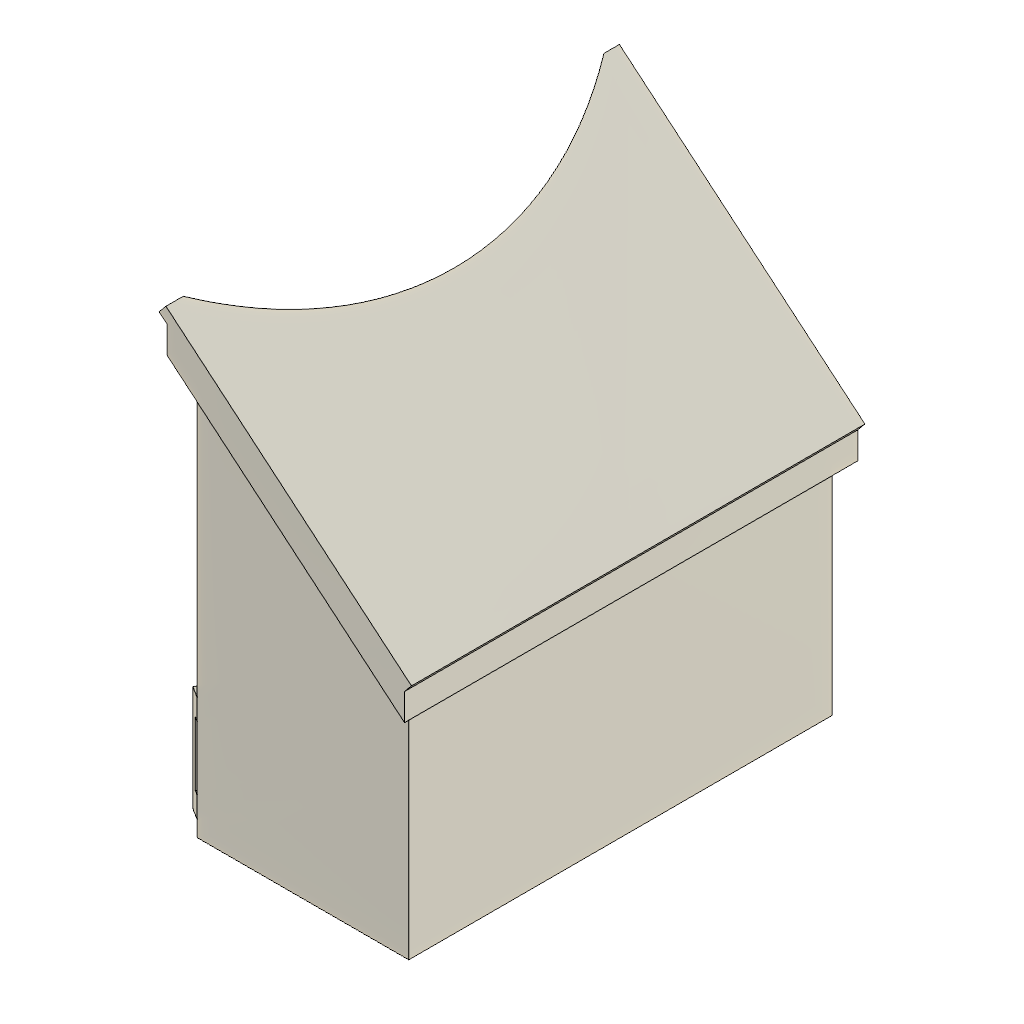
Tide Sensor Housing (Autodesk Fusion 360 design; units mm, degrees)
Autodesk Fusion 360 part; units mm, degrees
sketch "Sketch1" plane through (0, 0, 0) normal (0, 0, 1) x (1, 0, 0)
  line L0 (0, 0) -> (101.6, 0)
  line L1 (101.6, 0) -> (101.6, 203.2)
  line L2 (101.6, 203.2) -> (0, 203.2)
  line L3 (0, 203.2) -> (0, 0)
  circle A0 centre (-163.8957, 102.023) radius 193.04
  circle A1 centre (88.9, 119.38) radius 0.762
  circle A2 centre (88.9, 83.82) radius 0.762
  circle A3 centre (63.5, 119.38) radius 0.762
  circle A4 centre (63.5, 83.82) radius 0.762
  circle A5 centre (76.2, 101.6) radius 12.7
  line L4 (50.8, 127) -> (279.4, 127)
  line L5 (279.4, 127) -> (279.4, 76.2)
  line L6 (279.4, 76.2) -> (50.8, 76.2)
  line L7 (50.8, 76.2) -> (50.8, 127)
  line L8 (33.02, 175.26) -> (46.736, 175.26)
  line L9 (46.736, 175.26) -> (46.736, 180.34)
  line L10 (46.736, 180.34) -> (33.02, 180.34)
  line L11 (33.02, 180.34) -> (33.02, 175.26)
  line L12 (33.02, 175.26) -> (38.1, 175.26)
  line L13 (38.1, 175.26) -> (38.1, 165.1)
  line L14 (38.1, 165.1) -> (33.02, 165.1)
  line L15 (33.02, 165.1) -> (33.02, 175.26)
  line L16 (46.736, 175.26) -> (41.656, 175.26)
  line L17 (41.656, 175.26) -> (41.656, 165.1)
  line L18 (41.656, 165.1) -> (46.736, 165.1)
  line L19 (46.736, 165.1) -> (46.736, 175.26)
  line L20 (46.736, 180.34) -> (33.02, 180.34)
  line L21 (33.02, 175.26) -> (46.736, 175.26)
  line L22 (33.02, 180.34) -> (33.02, 175.26)
  line L23 (46.736, 175.26) -> (46.736, 180.34)
  line L24 (46.736, 165.1) -> (46.736, 175.26)
  line L25 (41.656, 175.26) -> (41.656, 165.1)
  line L26 (41.656, 165.1) -> (46.736, 165.1)
  line L27 (38.1, 175.26) -> (38.1, 165.1)
  line L28 (33.02, 165.1) -> (33.02, 175.26)
  line L29 (38.1, 165.1) -> (33.02, 165.1)
  line L30 (-163.8957, 102.023) -> (344.1043, 102.023)
  line L31 (38.1, 28.7859) -> (38.1, 38.9459)
  line L32 (33.02, 38.9459) -> (33.02, 28.7859)
  line L33 (33.02, 28.7859) -> (46.736, 28.7859)
  line L34 (38.1, 38.9459) -> (33.02, 38.9459)
  line L35 (41.656, 28.7859) -> (41.656, 38.9459)
  line L36 (41.656, 38.9459) -> (46.736, 38.9459)
  line L37 (46.736, 38.9459) -> (46.736, 28.7859)
  line L38 (46.736, 28.7859) -> (46.736, 23.7059)
  line L39 (46.736, 23.7059) -> (33.02, 23.7059)
  line L40 (33.02, 23.7059) -> (33.02, 28.7859)
  circle A6 centre (-163.8957, 102.023) radius 190.5
  circle A7 centre (-163.8957, 102.023) radius 186.69
  line L41 (-163.8957, 102.023) -> (0.9543, 203.8135)
  line L42 (-163.8957, 102.023) -> (0, 0)
  line L43 (-163.8957, 102.023) -> (19.05, 196.85)
  line L44 (-163.8957, 102.023) -> (19.05, 6.35)
  line L45 (4.9142, 13.7424) -> (7.165, 12.5654)
  line L46 (1.538, 15.508) -> (4.9142, 13.7424)
  line L47 (1.538, 15.508) -> (4.9142, 13.7424)
  line L48 (-163.8957, 102.023) -> (4.9142, 13.7424)
  point P0 (1.538, 15.508)
  point P1 (4.9142, 13.7424)
  point P2 (7.165, 12.5654)
  dimension "d1" = 101.6
  dimension "d2" = 203.2
  dimension "d3" = 386.08
  dimension "d4" = 1.524
  dimension "d5" = 1.524
  dimension "d6" = 1.524
  dimension "d7" = 1.524
  dimension "d8" = 25.4
  dimension "d9" = 228.6
  dimension "d10" = 50.8
  dimension "d76" = 13.716
  dimension "d77" = 5.08
  dimension "d78" = 5.08
  dimension "d79" = 10.16
  dimension "d80" = 5.08
  dimension "d81" = 10.16
  dimension "d82" = 13.716
  dimension "d83" = 5.08
  dimension "d84" = 5.08
  dimension "d85" = 10.16
  dimension "d86" = 5.08
  dimension "d87" = 10.16
  dimension "d88" = 508
  dimension "d89" = 13.716
  dimension "d90" = 5.08
  dimension "d91" = 10.16
  dimension "d92" = 13.716
  dimension "d93" = 5.08
  dimension "d94" = 5.08
  dimension "d95" = 10.16
  dimension "d96" = 5.08
  dimension "d97" = 10.16
  dimension "d109" = 381
  dimension "d110" = 373.38
  constraint horizontal L0
  constraint vertical L1
  constraint horizontal L2
  constraint vertical L3
  constraint coincident L0.start L3.end
  constraint horizontal L4
  constraint vertical L5
  constraint horizontal L6
  constraint vertical L7
  constraint horizontal L8
  constraint vertical L9
  constraint horizontal L10
  constraint vertical L11
  constraint horizontal L12
  constraint vertical L13
  constraint horizontal L14
  constraint vertical L15
  constraint horizontal L16
  constraint vertical L17
  constraint horizontal L18
  constraint vertical L19
  constraint horizontal L21
  constraint vertical L23
  constraint horizontal L20
  constraint vertical L22
  constraint vertical L27
  constraint horizontal L29
  constraint vertical L28
  constraint vertical L25
  constraint horizontal L26
  constraint vertical L24
  constraint coincident A0.centre L30.start
  constraint perpendicular L5 L30
  constraint concentric A0 A6
  constraint concentric A0 A7
  constraint coincident A7 P0
  constraint coincident L44 P0
  constraint coincident A6 P1
  constraint coincident L44 P1
  constraint coincident L44 P2
  constraint coincident A0 P2
  constraint coincident P1 L45.start
  constraint coincident P2 L45.end
  constraint coincident P0 L46.start
  measures "d1" distance of L0.start L0.end
  measures "d2" distance of L0.start L2.end
  measures "d3" diameter of A0
  measures "d4" diameter of A1
  measures "d5" diameter of A2
  measures "d6" diameter of A3
  measures "d7" diameter of A4
  measures "d8" diameter of A5
  measures "d9" distance of L4.start L4.end
  measures "d10" distance of L4.start L6.end
  measures "d76" distance of L8.start L8.end
  measures "d77" distance of L8.start L10.end
  measures "d78" distance of L8.start L12.end
  measures "d79" distance of L8.start L14.end
  measures "d80" distance of L8.end L16.end
  measures "d81" distance of L8.end L18.end
  measures "d82" distance of L8.start L8.end
  measures "d83" distance of L10.end L8.start
  measures "d84" distance of L8.start L12.end
  measures "d85" distance of L8.start L14.end
  measures "d86" distance of L8.end L16.end
  measures "d87" distance of L8.end L18.end
  measures "d88" distance of A0.centre L30.end
  measures "d89" distance of L32.end L33.end
  measures "d90" distance of L39.end L32.end
  measures "d91" distance of L32.end L32.start
  measures "d92" distance of L32.end L33.end
  measures "d93" distance of L39.end L32.end
  measures "d94" distance of L32.end L31.start
  measures "d95" distance of L32.end L32.start
  measures "d96" distance of L33.end L35.start
  measures "d97" distance of L33.end L36.end
  measures "d109" diameter of A6
  measures "d110" diameter of A7
extrude "Extrude1" add sketch "Sketch1" along normal blind 203.2 thin wall 5.08 inside contours L0 L1 L3 A0 L6 L7 L30 | L1 A5 L6 L7 L30 | L1 A5 L4 L7 L30 | L1 L2 A0 L4 L7 L30 | A5 L30 | A5 L30 | A1 | A2 | A3 | A4 | L8 L9 L10 L11 L12 L16 L20 L21 L22 L23 | L8 L12 L13 L14 L15 L21 L27 L28 L29 | L8 L16 L17 L18 L19 L21 L24 L25 L26 | L31 L32 L33 L34 | L33 L38 L39 L40 | L33 L35 L36 L37 makes body 1
extrude "Extrude2" add sketch "Sketch1" against normal blind 7.62 contours L0 L1 L3 A0 L6 L7 L30 | L1 A5 L6 L7 L30 | L1 A5 L4 L7 L30 | L1 L2 A0 L4 L7 L30 | L8 L9 L10 L11 L12 L16 L20 L21 L22 L23 | L8 L12 L13 L14 L15 L21 L27 L28 L29 | L8 L16 L17 L18 L19 L21 L24 L25 L26 | L31 L32 L33 L34 | L33 L38 L39 L40 | L33 L35 L36 L37 bodies 1
sketch "Sketch2" plane through (0, 0, 0) normal (0, 0, 1) x (1, 0, 0)
  line L0 (0, 0) -> (228.6, 0)
  line L1 (228.6, 0) -> (228.6, 50.8)
  line L2 (228.6, 50.8) -> (0, 50.8)
  line L3 (0, 50.8) -> (0, 0)
  circle A0 centre (25.4, 25.4) radius 12.7
  circle A1 centre (203.2, 25.4) radius 8.128
  circle A2 centre (203.2, 25.4) radius 8.128
  line L4 (228.6, 50.8) -> (0, 50.8)
  circle A3 centre (25.4, 127) radius 12.7
  line L5 (-5.08, 96.52) -> (233.68, 96.52)
  line L6 (233.68, 96.52) -> (233.68, 157.48)
  line L7 (233.68, 157.48) -> (-5.08, 157.48)
  line L8 (-5.08, 157.48) -> (-5.08, 96.52)
  circle A4 centre (220.98, 43.18) radius 5.08
  circle A5 centre (220.98, 7.62) radius 5.08
  circle A6 centre (220.98, 43.18) radius 1.651
  circle A7 centre (220.98, 7.62) radius 1.651
  circle A8 centre (55.88, 7.62) radius 5.08
  circle A9 centre (55.88, 7.62) radius 1.651
  circle A10 centre (55.88, 43.18) radius 5.08
  circle A11 centre (55.88, 43.18) radius 1.651
  circle A12 centre (220.98, 144.78) radius 2.54
  circle A13 centre (220.98, 109.22) radius 2.54
  circle A14 centre (55.88, 144.78) radius 2.54
  circle A15 centre (55.88, 109.22) radius 2.54
  line L9 (-5.08, 157.48) -> (-5.08, 96.52)
  line L10 (233.68, 157.48) -> (-5.08, 157.48)
  circle A16 centre (25.4, 127) radius 12.7
  circle A17 centre (220.98, 109.22) radius 2.54
  circle A18 centre (220.98, 144.78) radius 2.54
  circle A19 centre (55.88, 144.78) radius 2.54
  circle A20 centre (55.88, 109.22) radius 2.54
  circle A21 centre (12.7, 144.78) radius 1.27
  circle A22 centre (38.1, 144.78) radius 1.27
  circle A23 centre (12.7, 109.22) radius 1.27
  circle A24 centre (38.1, 109.22) radius 1.27
  dimension "d20" = 228.6
  dimension "d21" = 50.8
  dimension "d22" = 25.4
  dimension "d23" = 16.256
  dimension "d24" = 16.256
  dimension "d28" = 25.4
  dimension "d29" = 10.16
  dimension "d30" = 10.16
  dimension "d31" = 3.302
  dimension "d32" = 3.302
  dimension "d33" = 10.16
  dimension "d34" = 10.16
  dimension "d35" = 3.302
  dimension "d36" = 3.302
  dimension "d37" = 5.08
  dimension "d38" = 5.08
  dimension "d40" = 5.08
  dimension "d41" = 5.08
  dimension "d53" = 25.4
  dimension "d54" = 5.08
  dimension "d55" = 5.08
  dimension "d56" = 5.08
  dimension "d57" = 5.08
  dimension "d63" = 2.54
  dimension "d64" = 2.54
  dimension "d65" = 2.54
  dimension "d66" = 2.54
  constraint horizontal L0
  constraint vertical L1
  constraint horizontal L2
  constraint vertical L3
  constraint coincident L0.start L3.end
  constraint horizontal L4
  constraint horizontal L5
  constraint vertical L6
  constraint horizontal L7
  constraint vertical L8
  constraint concentric A4 A6
  constraint concentric A5 A7
  constraint concentric A10 A11
  constraint concentric A8 A9
  constraint horizontal L10
  constraint vertical L9
  measures "d20" distance of L0.start L0.end
  measures "d21" distance of L0.start L2.end
  measures "d22" diameter of A0
  measures "d23" diameter of A1
  measures "d24" diameter of A2
  measures "d28" diameter of A3
  measures "d29" diameter of A4
  measures "d30" diameter of A5
  measures "d31" diameter of A6
  measures "d32" diameter of A7
  measures "d33" diameter of A10
  measures "d34" diameter of A8
  measures "d35" diameter of A11
  measures "d36" diameter of A9
  measures "d37" diameter of A12
  measures "d38" diameter of A13
  measures "d40" diameter of A14
  measures "d41" diameter of A15
  measures "d53" diameter of A16
  measures "d54" diameter of A18
  measures "d55" diameter of A17
  measures "d56" diameter of A19
  measures "d57" diameter of A20
  measures "d63" diameter of A21
  measures "d64" diameter of A22
  measures "d65" diameter of A23
  measures "d66" diameter of A24
extrude "Extrude12" add sketch "Sketch1" along normal blind 76.2 separate body contours L8 L9 L10 L11 L12 L16 L20 L21 L22 L23 | L8 L12 L13 L14 L15 L21 L27 L28 L29 | L8 L16 L17 L18 L19 L21 L24 L25 L26 | L31 L32 L33 L34 | L33 L38 L39 L40 | L33 L35 L36 L37 makes body 2 at (33.02, 175.26, 25.4) makes body 3 at (33.02, 33.8659, 50.8)
sketch "Sketch3" plane through (0, 0, 0) normal (0, 1, 0) x (1, 0, 0)
  line L0 (0.3158, -203.2) -> (155.9761, -72.5856)
  line L1 (0.3158, -203.2) -> (203.5158, -203.2) construction
  line L2 (0.3158, -203.2) -> (101.6, -203.2)
  line L3 (101.6, 0) -> (101.6, -203.2)
  line L4 (101.6, -111.76) -> (101.6, -203.2)
  point P0 (101.6, -203.2)
  point P1 (101.6, -203.2)
  dimension "d105" = 40
  dimension "d106" = 203.2
  constraint horizontal L1
  constraint coincident L3 L4.start
  measures "d105" angle of L0 L1
  measures "d106" distance of L0.start L0.end
extrude "Extrude4" add sketch "Sketch2" along normal blind 25.4 thin wall 5.08 inside separate body contours L0 L1 L2 L3 L4 | A0 | A1 A2 | A4 | A5 | A6 | A7 | A8 | A9 | A10 | A11 makes body 4
extrude "Extrude5" add sketch "Sketch2" against normal blind 5.08 separate body contours L0 L1 L2 L3 L4 | A0 | A4 | A5 | A6 | A7 | A8 | A9 | A10 | A11 makes body 5
extrude "Extrude6" add sketch "Sketch2" along normal blind 25.4 contours A4 | A5 | A8 | A10 bodies 4 5
extrude "Extrude9" add sketch "Sketch2" along normal blind 5.08 separate body contours L5 L6 L7 L8 L9 L10 makes body 6
extrude "Extrude10" add sketch "Sketch2" against normal blind 10.16 thin wall 5.08 inside separate body contours A3 A16 | L5 L6 L7 L8 L9 L10 | A12 A18 | A13 A17 | A14 A19 | A15 A20 | A21 | A22 | A23 | A24 makes body 7
sketch "Sketch4" plane through (0, 0, 0) normal (0, -1, 0) x (1, 0, 0)
  line L0 (101.6, -7.62) -> (101.6, 203.2)
  line L1 (101.6, 203.2) -> (0, 203.2)
  line L2 (0, -7.62) -> (101.6, -7.62)
  line L3 (-25.4, 224.5131) -> (139.7, 85.9778)
  line L4 (0, 203.2) -> (152.5992, 203.2) construction
  line L5 (0, 203.2) -> (0, -7.62)
  line L6 (116.7452, 94.5635) -> (116.7452, 105.2392)
  line L7 (-25.4, 228.6) -> (139.7, 228.6)
  line L8 (139.7, 228.6) -> (139.7, -12.3567)
  line L9 (139.7, -12.3567) -> (-25.4, -12.3567)
  line L10 (-25.4, -12.3567) -> (-25.4, 228.6)
  line L11 (-25.4, 211.8131) -> (139.7, 73.2778)
  dimension "d72" = 40
  dimension "d73" = 152.4
  constraint horizontal L4
  constraint coincident L1.end L4.start
  constraint vertical L6
  constraint horizontal L7
  constraint vertical L8
  constraint horizontal L9
  constraint vertical L10
  constraint coincident L1.end L3
  constraint coincident L10 L3.start
  constraint coincident L8 L3.end
  constraint coincident L6.end L3
  measures "d72" angle of L3 L4
  measures "d73" distance of L1.end L6.end
extrude "Extrude11" cut sketch "Sketch4" against normal blind 254 contours L0 L1 L3 | L0 L1 L3 L7 L8 L10 bodies 1
extrude "Extrude16" add sketch "Sketch1" along normal blind 10.16 separate body contours L3 A0 A6 L42 | L3 A0 A6 L44 L45 | L3 A6 A7 L42 | L3 A6 A7 L44 L46 L47 L48 | A0 L30 A6 L44 L45 | L2 L3 A0 A6 L41 | L30 A6 A7 L44 L46 L47 L48 | A0 L30 A6 L43 | L2 L3 A0 A6 L43 | L3 A6 A7 L41 | L30 A6 A7 L43 | L3 A6 A7 L43 makes body 8
copy_body "CopyPasteBodies1" bodies 8 makes body 9
move_body "Move1" bodies 9 to x (1, 0, 0) y (0, 1, 0) z (0, 0, 1) at (0, 0, 40.64)
extrude "Extrude17" add sketch "Sketch1" along normal blind 50.8 separate body contours L3 A6 A7 L42 | L3 A6 A7 L44 L46 L47 L48 | L30 A6 A7 L44 L46 L47 L48 | L3 A6 A7 L41 | L30 A6 A7 L43 | L3 A6 A7 L43 makes body 10
pipe "Pipe1" add diameter 2.54 path "Sketch1" along L44 separate body makes body 11
pipe "Pipe2" add diameter 3.556 path "Sketch1" along L45 separate body makes body 12
pipe "Pipe3" add diameter 5.588 path "Sketch1" along L48 bodies 11 12
move_body "Move2" bodies 11 to x (1, 0, 0) y (0, 1, 0) z (0, 0, 1) at (0, 0, 5.08)
copy_body "CopyPasteBodies2" bodies 11 makes body 13
move_body "Move3" bodies 13 to x (1, 0, 0) y (0, 1, 0) z (0, 0, 1) at (0, 0, 40.64)
combine "Combine1" operation add target body 13 tool bodies 11 makes body 14 at (-106.9233, 73.9394, 7.427)
sketch "Sketch12" plane through (0, 0, 0) normal (0, 1, 0) x (1, 0, 0)
  line L0 (-417.83, -353.06, 101.6) -> (443.23, -353.06, 101.6)
  line L1 (443.23, -353.06, 101.6) -> (443.23, 275.59, 101.6)
  line L2 (443.23, 275.59, 101.6) -> (-417.83, 275.59, 101.6)
  line L3 (-417.83, 275.59, 101.6) -> (-417.83, -353.06, 101.6)
  line L4 (-165.1, -46.99, 101.6) -> (-165.1, -5.08, 101.6)
  line L5 (-165.1, -5.08, 101.6) -> (-165.1, 45.72, 101.6)
  line L6 (-165.1, 45.72, 101.6) -> (-165.1, -105.41, 101.6)
copy_body "CopyPasteBodies3" bodies 13 14 makes body 15 makes body 16
move_body "Move4" bodies 15 16 to x (0.576432, 0.817145, 0) y (-0.817145, 0.576432, 0) z (0, 0, 1) at (13.0909, 177.9451, 0)
copy_body "CopyPasteBodies4" bodies 13 14 16 15 makes body 17 makes body 18 makes body 19 makes body 20
move_body "Move5" bodies 17 18 19 20 to x (1, 0, 0) y (0, 1, 0) z (0, 0, 1) at (0, 0, 127)
combine "Combine2" operation cut target body 1 tool bodies 14 17 19 20 16 18 13 15 keep tools
combine "Combine3" operation add target body 10 tool bodies 9 8
combine "Combine4" operation cut target body 10 tool bodies 16 14 15 13 keep tools
sketch "Sketch13" plane through (0, 0, 0) normal (0, 0, 1) x (1, 0, 0)
  circle A0 centre (-163.9235, 102.0591) radius 193.04
  line L0 (0, 0) -> (101.6, 0)
  line L1 (101.6, 0) -> (101.6, 203.2)
  line L2 (101.6, 203.2) -> (0, 203.2)
  line L3 (0, 203.2) -> (0, 0)
  dimension "d142" = 386.08
  constraint horizontal L0
  constraint vertical L1
  constraint horizontal L2
  constraint vertical L3
  constraint coincident L0.start L3.end
  measures "d142" diameter of A0
extrude "Extrude25" add sketch "Sketch1" along normal blind 215.9 thin wall 5.08 outside separate body contours L0 L1 L3 A0 L6 L7 L30 | L1 A5 L6 L7 L30 | L1 A5 L4 L7 L30 | L1 L2 A0 L4 L7 L30 | A5 L30 | A5 L30 | A1 | A2 | A3 | A4 | L8 L9 L10 L11 L12 L16 L20 L21 L22 L23 | L8 L12 L13 L14 L15 L21 L27 L28 L29 | L8 L16 L17 L18 L19 L21 L24 L25 L26 | L31 L32 L33 L34 | L33 L38 L39 L40 | L33 L35 L36 L37 makes body 21
extrude "Extrude26" cut sketch "Sketch4" along normal mid plane 508 contours L0 L1 L3 | L0 L1 L3 L7 L8 L10 bodies 21
extrude "Extrude27" cut sketch "Sketch4" along normal mid plane 508 contours L0 L2 L5 L11 | L0 L2 L5 L8 L9 L10 L11 bodies 21
sketch "Sketch14" plane through (100.0565, 0, 119.2427) normal (0.642788, 0, 0.766044) x (0, 1, 0)
  line L0 (0, 130.6144) -> (0.0297, 130.6144)
  ellipse E0 centre (102.023, 344.5651) end of major axis (102.023, 92.5693) minor radius 193.04 (0.0297, 130.6144) -> (203.2, 129.955) ccw
  line L1 (203.2, 129.955) -> (203.2, -2.0149)
  line L2 (203.2, -2.0149) -> (0, -2.0149)
  line L3 (0, -2.0149) -> (0, 130.6144)
  line L4 (1.4918, 137.2459) -> (-5.08, 137.2459)
  line L5 (-5.08, 137.2459) -> (-5.08, -8.6464)
  line L6 (-5.08, -8.6464) -> (208.28, -8.6464)
  line L7 (208.28, -8.6464) -> (208.28, 142.1706)
  ellipse E1 centre (102.023, 344.5651) end of major axis (102.023, 99.2008) minor radius 187.96 (1.4918, 137.2459) -> (208.28, 142.1706) ccw
  line L8 (-5.08, -8.6464) -> (208.28, -8.6464)
  line L9 (208.28, -8.6464) -> (208.28, 142.1706)
  line L10 (208.28, 142.1706) -> (-5.08, 142.1706)
  line L11 (-5.08, 142.1706) -> (-5.08, -8.6464)
  constraint horizontal L8
  constraint vertical L9
  constraint horizontal L10
  constraint vertical L11
  constraint coincident L7.end L9.end
  constraint coincident L5.end L6.start
extrude "Extrude28" add sketch "Sketch14" along normal blind 5.08 contours L0 E0 L1 L2 L3 | L4 L5 L6 L7 E1 L8 L9 L11 | L4 E1 L10 L11 bodies 21
extrude "Extrude29" cut sketch "Sketch1" along normal mid plane 508 contours L3 A7 L42 L44 L48 | L3 A7 L44 L48 | A7 L41 L42 | L3 L30 L44 L48 | L3 L30 A7 L44 L48 | L3 A7 L41 L43 | L3 L30 L43 | L3 L30 A7 L43 | L3 A7 L43 bodies 21
scale "Scale1" factor 1.02 about (0.5051, 203.2, 190.0761) bodies 21
hidden bodies 4 6 7 13 14 15 16 17 18 19 20
named bodies: "Main Box", "Extension Box Bottom", "Extension Box Topa", "Extension Box Topb", "Main Boxb", "Main Boxc", "Strap a", "Strap b", "Strap", "Top"
